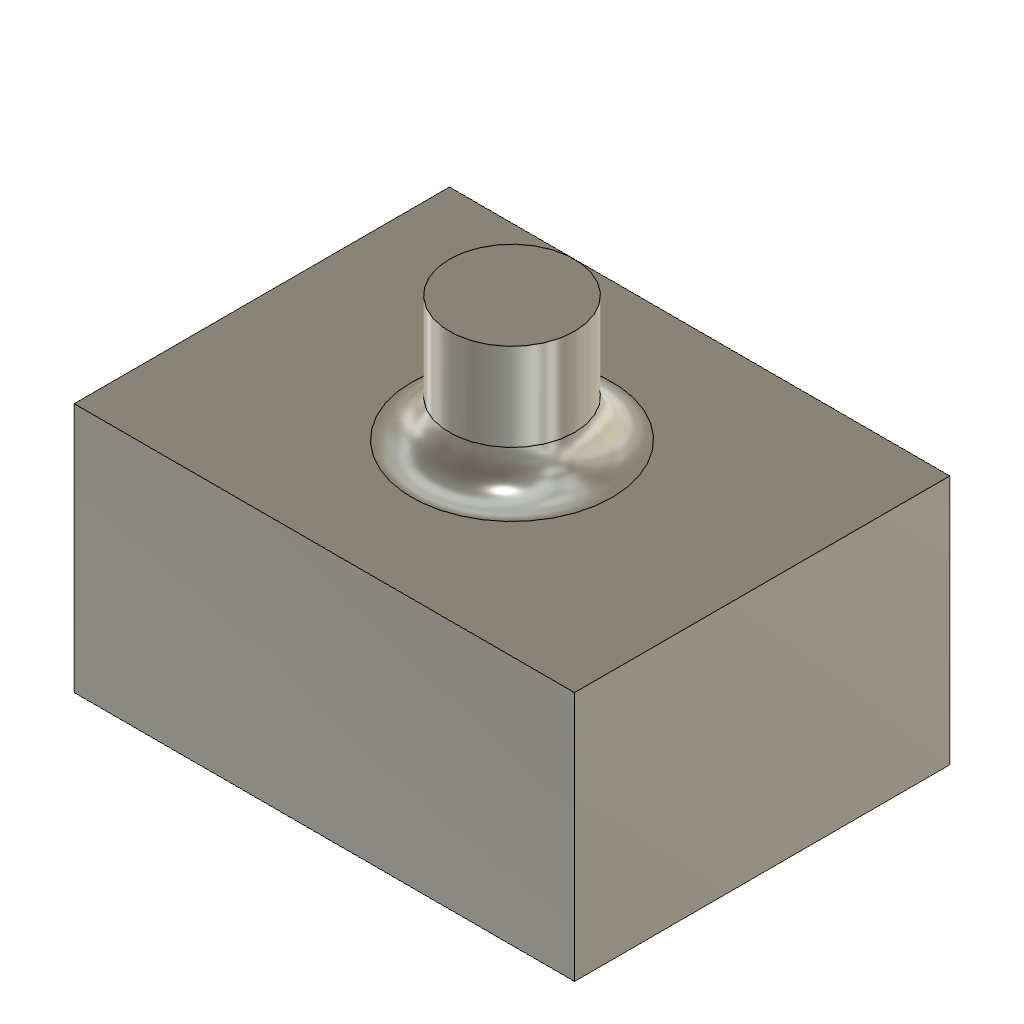
vendor_RoundBossBase (Autodesk Fusion 360 design; units mm, degrees)
Autodesk Fusion 360 part; units mm, degrees
sketch "Base sketch" plane through (0, 0, 0) normal (0, 0, 1) x (1, 0, 0)
  line L0 (0, 0) -> (40, 0)
  line L1 (40, 0) -> (40, 30)
  line L2 (40, 30) -> (0, 30)
  line L3 (0, 30) -> (0, 0)
extrude "Base extrude" add sketch "Base sketch" along normal blind 20
sketch "Boss sketch" plane through (0, 0, 0) normal (0, 0, 1) x (1, 0, 0)
  circle A0 centre (20, 15) radius 5
extrude "Boss" add sketch "Boss sketch" along normal blind 30
fillet "Boss round" radius 3 1 edges at (15.3384, 16.8081, 20)
equation "height = 20.0 mm"
